Autodesk Fusion 360 part; units mm, degrees
(part 4 of 4)
  line L918 (235.694, -72.9326) -> (235.694, -74.9331)
  line L919 (235.694, -74.9331) -> (221.695, -74.9331)
  line L920 (221.695, -74.9331) -> (221.695, -72.9326)
  line L921 (221.695, -72.9326) -> (220.894, -72.9326)
  line L922 (220.894, -72.9326) -> (220.894, -69.8334)
  line L923 (220.894, -69.8334) -> (221.695, -69.8334)
  line L924 (221.695, -69.8334) -> (221.695, -64.0334)
  line L925 (221.695, -64.0334) -> (220.894, -64.0334)
  line L926 (220.894, -64.0334) -> (220.894, -60.9328)
  line L927 (220.894, -60.9328) -> (221.695, -60.9328)
  line L928 (135.97, -79.9828) -> (135.97, -77.9838)
  line L929 (135.97, -77.9838) -> (149.969, -77.9838)
  line L930 (149.969, -77.9838) -> (149.969, -79.9828)
  line L931 (149.969, -79.9828) -> (150.77, -79.9828)
  line L932 (150.77, -79.9828) -> (150.77, -83.0834)
  line L933 (150.77, -83.0834) -> (149.969, -83.0834)
  line L934 (149.969, -83.0834) -> (149.969, -88.8834)
  line L935 (149.969, -88.8834) -> (150.77, -88.8834)
  line L936 (150.77, -88.8834) -> (150.77, -91.9826)
  line L937 (150.77, -91.9826) -> (149.969, -91.9826)
  line L938 (149.969, -91.9826) -> (149.969, -93.9831)
  line L939 (149.969, -93.9831) -> (135.97, -93.9831)
  line L940 (135.97, -93.9831) -> (135.97, -91.9826)
  line L941 (135.97, -91.9826) -> (135.169, -91.9826)
  line L942 (135.169, -91.9826) -> (135.169, -88.8834)
  line L943 (135.169, -88.8834) -> (135.97, -88.8834)
  line L944 (135.97, -88.8834) -> (135.97, -83.0834)
  line L945 (135.97, -83.0834) -> (135.169, -83.0834)
  line L946 (135.169, -83.0834) -> (135.169, -79.9828)
  line L947 (135.169, -79.9828) -> (135.97, -79.9828)
  line L948 (69.2947, -60.9328) -> (69.2947, -58.9338)
  line L949 (69.2947, -58.9338) -> (83.294, -58.9338)
  line L950 (83.294, -58.9338) -> (83.294, -60.9328)
  line L951 (83.294, -60.9328) -> (84.0948, -60.9328)
  line L952 (84.0948, -60.9328) -> (84.0948, -64.0334)
  line L953 (84.0948, -64.0334) -> (83.294, -64.0334)
  line L954 (83.294, -64.0334) -> (83.294, -69.8334)
  line L955 (83.294, -69.8334) -> (84.0948, -69.8334)
  line L956 (84.0948, -69.8334) -> (84.0948, -72.9326)
  line L957 (84.0948, -72.9326) -> (83.294, -72.9326)
  line L958 (83.294, -72.9326) -> (83.294, -74.9331)
  line L959 (83.294, -74.9331) -> (69.2947, -74.9331)
  line L960 (69.2947, -74.9331) -> (69.2947, -72.9326)
  line L961 (69.2947, -72.9326) -> (68.4939, -72.9326)
  line L962 (68.4939, -72.9326) -> (68.4939, -69.8334)
  line L963 (68.4939, -69.8334) -> (69.2947, -69.8334)
  line L964 (69.2947, -69.8334) -> (69.2947, -64.0334)
  line L965 (69.2947, -64.0334) -> (68.4939, -64.0334)
  line L966 (68.4939, -64.0334) -> (68.4939, -60.9328)
  line L967 (68.4939, -60.9328) -> (69.2947, -60.9328)
  line L968 (169.307, -41.8828) -> (169.307, -39.8838)
  line L969 (169.307, -39.8838) -> (183.307, -39.8838)
  line L970 (183.307, -39.8838) -> (183.307, -41.8828)
  line L971 (183.307, -41.8828) -> (184.106, -41.8828)
  line L972 (184.106, -41.8828) -> (184.106, -44.9834)
  line L973 (184.106, -44.9834) -> (183.307, -44.9834)
  line L974 (183.307, -44.9834) -> (183.307, -50.7834)
  line L975 (183.307, -50.7834) -> (184.106, -50.7834)
  line L976 (184.106, -50.7834) -> (184.106, -53.8826)
  line L977 (184.106, -53.8826) -> (183.307, -53.8826)
  line L978 (183.307, -53.8826) -> (183.307, -55.8831)
  line L979 (183.307, -55.8831) -> (169.307, -55.8831)
  line L980 (169.307, -55.8831) -> (169.307, -53.8826)
  line L981 (169.307, -53.8826) -> (168.506, -53.8826)
  line L982 (168.506, -53.8826) -> (168.506, -50.7834)
  line L983 (168.506, -50.7834) -> (169.307, -50.7834)
  line L984 (169.307, -50.7834) -> (169.307, -44.9834)
  line L985 (169.307, -44.9834) -> (168.506, -44.9834)
  line L986 (168.506, -44.9834) -> (168.506, -41.8828)
  line L987 (168.506, -41.8828) -> (169.307, -41.8828)
  line L988 (150.257, -41.8828) -> (150.257, -39.8838)
  line L989 (150.257, -39.8838) -> (164.257, -39.8838)
  line L990 (164.257, -39.8838) -> (164.257, -41.8828)
  line L991 (164.257, -41.8828) -> (165.056, -41.8828)
  line L992 (165.056, -41.8828) -> (165.056, -44.9834)
  line L993 (165.056, -44.9834) -> (164.257, -44.9834)
  line L994 (164.257, -44.9834) -> (164.257, -50.7834)
  line L995 (164.257, -50.7834) -> (165.056, -50.7834)
  line L996 (165.056, -50.7834) -> (165.056, -53.8826)
  line L997 (165.056, -53.8826) -> (164.257, -53.8826)
  line L998 (164.257, -53.8826) -> (164.257, -55.8831)
  line L999 (164.257, -55.8831) -> (150.257, -55.8831)
  line L1000 (150.257, -55.8831) -> (150.257, -53.8826)
  line L1001 (150.257, -53.8826) -> (149.456, -53.8826)
  line L1002 (149.456, -53.8826) -> (149.456, -50.7834)
  line L1003 (149.456, -50.7834) -> (150.257, -50.7834)
  line L1004 (150.257, -50.7834) -> (150.257, -44.9834)
  line L1005 (150.257, -44.9834) -> (149.456, -44.9834)
  line L1006 (149.456, -44.9834) -> (149.456, -41.8828)
  line L1007 (149.456, -41.8828) -> (150.257, -41.8828)
  line L1008 (257.412, -41.8828) -> (257.412, -39.8838)
  line L1009 (257.412, -39.8838) -> (271.413, -39.8838)
  line L1010 (271.413, -39.8838) -> (271.413, -41.8828)
  line L1011 (271.413, -41.8828) -> (272.212, -41.8828)
  line L1012 (272.212, -41.8828) -> (272.212, -44.9834)
  line L1013 (272.212, -44.9834) -> (271.413, -44.9834)
  line L1014 (271.413, -44.9834) -> (271.413, -45.5828)
  line L1015 (271.413, -45.5828) -> (272.937, -45.5828)
  line L1016 (272.937, -45.5828) -> (272.937, -41.1138)
  line L1017 (272.937, -41.1138) -> (274.662, -41.1138)
  line L1018 (274.662, -41.1138) -> (274.662, -39.9136)
  line L1019 (274.662, -39.9136) -> (277.963, -39.9136)
  line L1020 (277.963, -39.9136) -> (277.963, -41.1138)
  line L1021 (277.963, -41.1138) -> (279.688, -41.1138)
  line L1022 (279.688, -41.1138) -> (279.688, -47.3837)
  line L1023 (279.688, -47.3837) -> (280.512, -47.3837)
  line L1024 (280.512, -47.3837) -> (280.512, -50.1826)
  line L1025 (280.512, -50.1826) -> (279.688, -50.1826)
  line L1026 (279.688, -50.1826) -> (279.688, -53.4127)
  line L1027 (279.688, -53.4127) -> (272.937, -53.4127)
  line L1028 (272.937, -53.4127) -> (272.937, -50.1826)
  line L1029 (272.937, -50.1826) -> (271.413, -50.1826)
  line L1030 (271.413, -50.1826) -> (271.413, -50.7834)
  line L1031 (271.413, -50.7834) -> (272.212, -50.7834)
  line L1032 (272.212, -50.7834) -> (272.212, -53.8826)
  line L1033 (272.212, -53.8826) -> (271.413, -53.8826)
  line L1034 (271.413, -53.8826) -> (271.413, -55.8831)
  line L1035 (271.413, -55.8831) -> (257.412, -55.8831)
  line L1036 (257.412, -55.8831) -> (257.412, -53.8826)
  line L1037 (257.412, -53.8826) -> (256.611, -53.8826)
  line L1038 (256.611, -53.8826) -> (256.611, -50.7834)
  line L1039 (256.611, -50.7834) -> (257.412, -50.7834)
  line L1040 (257.412, -50.7834) -> (257.412, -50.1826)
  line L1041 (257.412, -50.1826) -> (255.888, -50.1826)
  line L1042 (255.888, -50.1826) -> (255.888, -53.4127)
  line L1043 (255.888, -53.4127) -> (249.137, -53.4127)
  line L1044 (249.137, -53.4127) -> (249.137, -50.1826)
  line L1045 (249.137, -50.1826) -> (248.313, -50.1826)
  line L1046 (248.313, -50.1826) -> (248.313, -47.3837)
  line L1047 (248.313, -47.3837) -> (249.137, -47.3837)
  line L1048 (249.137, -47.3837) -> (249.137, -41.1138)
  line L1049 (249.137, -41.1138) -> (250.862, -41.1138)
  line L1050 (250.862, -41.1138) -> (250.862, -39.9136)
  line L1051 (250.862, -39.9136) -> (254.161, -39.9136)
  line L1052 (254.161, -39.9136) -> (254.161, -41.1138)
  line L1053 (254.161, -41.1138) -> (255.888, -41.1138)
  line L1054 (255.888, -41.1138) -> (255.888, -45.5828)
  line L1055 (255.888, -45.5828) -> (257.412, -45.5828)
  line L1056 (257.412, -45.5828) -> (257.412, -44.9834)
  line L1057 (257.412, -44.9834) -> (256.611, -44.9834)
  line L1058 (256.611, -44.9834) -> (256.611, -41.8828)
  line L1059 (256.611, -41.8828) -> (257.412, -41.8828)
  line L1060 (83.5822, -22.8327) -> (83.5822, -20.8336)
  line L1061 (83.5822, -20.8336) -> (97.5815, -20.8336)
  line L1062 (97.5815, -20.8336) -> (97.5815, -22.8327)
  line L1063 (97.5815, -22.8327) -> (98.3809, -22.8327)
  line L1064 (98.3809, -22.8327) -> (98.3809, -25.9333)
  line L1065 (98.3809, -25.9333) -> (97.5815, -25.9333)
  line L1066 (97.5815, -25.9333) -> (97.5815, -31.7348)
  line L1067 (97.5815, -31.7348) -> (98.3809, -31.7348)
  line L1068 (98.3809, -31.7348) -> (98.3809, -34.8327)
  line L1069 (98.3809, -34.8327) -> (97.5815, -34.8327)
  line L1070 (97.5815, -34.8327) -> (97.5815, -36.833)
  line L1071 (97.5815, -36.833) -> (83.5822, -36.833)
  line L1072 (83.5822, -36.833) -> (83.5822, -34.8327)
  line L1073 (83.5822, -34.8327) -> (82.7814, -34.8327)
  line L1074 (82.7814, -34.8327) -> (82.7814, -31.7348)
  line L1075 (82.7814, -31.7348) -> (83.5822, -31.7348)
  line L1076 (83.5822, -31.7348) -> (83.5822, -25.9333)
  line L1077 (83.5822, -25.9333) -> (82.7814, -25.9333)
  line L1078 (82.7814, -25.9333) -> (82.7814, -22.8327)
  line L1079 (82.7814, -22.8327) -> (83.5822, -22.8327)
  line L1080 (288.37, -22.8327) -> (288.37, -20.8336)
  line L1081 (288.37, -20.8336) -> (302.369, -20.8336)
  line L1082 (302.369, -20.8336) -> (302.369, -22.8327)
  line L1083 (302.369, -22.8327) -> (303.17, -22.8327)
  line L1084 (303.17, -22.8327) -> (303.17, -25.9333)
  line L1085 (303.17, -25.9333) -> (302.369, -25.9333)
  line L1086 (302.369, -25.9333) -> (302.369, -31.7348)
  line L1087 (302.369, -31.7348) -> (303.17, -31.7348)
  line L1088 (303.17, -31.7348) -> (303.17, -34.8327)
  line L1089 (303.17, -34.8327) -> (302.369, -34.8327)
  line L1090 (302.369, -34.8327) -> (302.369, -36.833)
  line L1091 (302.369, -36.833) -> (288.37, -36.833)
  line L1092 (288.37, -36.833) -> (288.37, -34.8327)
  line L1093 (288.37, -34.8327) -> (287.569, -34.8327)
  line L1094 (287.569, -34.8327) -> (287.569, -31.7348)
  line L1095 (287.569, -31.7348) -> (288.37, -31.7348)
  line L1096 (288.37, -31.7348) -> (288.37, -25.9333)
  line L1097 (288.37, -25.9333) -> (287.569, -25.9333)
  line L1098 (287.569, -25.9333) -> (287.569, -22.8327)
  line L1099 (287.569, -22.8327) -> (288.37, -22.8327)
  line L1100 (269.32, -22.8327) -> (269.32, -20.8336)
  line L1101 (269.32, -20.8336) -> (283.319, -20.8336)
  line L1102 (283.319, -20.8336) -> (283.319, -22.8327)
  line L1103 (283.319, -22.8327) -> (284.12, -22.8327)
  line L1104 (284.12, -22.8327) -> (284.12, -25.9333)
  line L1105 (284.12, -25.9333) -> (283.319, -25.9333)
  line L1106 (283.319, -25.9333) -> (283.319, -31.7348)
  line L1107 (283.319, -31.7348) -> (284.12, -31.7348)
  line L1108 (284.12, -31.7348) -> (284.12, -34.8327)
  line L1109 (284.12, -34.8327) -> (283.319, -34.8327)
  line L1110 (283.319, -34.8327) -> (283.319, -36.833)
  line L1111 (283.319, -36.833) -> (269.32, -36.833)
  line L1112 (269.32, -36.833) -> (269.32, -34.8327)
  line L1113 (269.32, -34.8327) -> (268.519, -34.8327)
  line L1114 (268.519, -34.8327) -> (268.519, -31.7348)
  line L1115 (268.519, -31.7348) -> (269.32, -31.7348)
  line L1116 (269.32, -31.7348) -> (269.32, -25.9333)
  line L1117 (269.32, -25.9333) -> (268.519, -25.9333)
  line L1118 (268.519, -25.9333) -> (268.519, -22.8327)
  line L1119 (268.519, -22.8327) -> (269.32, -22.8327)
  line L1120 (250.27, -3.7827) -> (250.27, -1.7836)
  line L1121 (250.27, -1.7836) -> (264.269, -1.7836)
  line L1122 (264.269, -1.7836) -> (264.269, -3.7827)
  line L1123 (264.269, -3.7827) -> (265.07, -3.7827)
  line L1124 (265.07, -3.7827) -> (265.07, -6.8833)
  line L1125 (265.07, -6.8833) -> (264.269, -6.8833)
  line L1126 (264.269, -6.8833) -> (264.269, -12.6848)
  line L1127 (264.269, -12.6848) -> (265.07, -12.6848)
  line L1128 (265.07, -12.6848) -> (265.07, -15.7827)
  line L1129 (265.07, -15.7827) -> (264.269, -15.7827)
  line L1130 (264.269, -15.7827) -> (264.269, -17.7831)
  line L1131 (264.269, -17.7831) -> (250.27, -17.7831)
  line L1132 (250.27, -17.7831) -> (250.27, -15.7827)
  line L1133 (250.27, -15.7827) -> (249.469, -15.7827)
  line L1134 (249.469, -15.7827) -> (249.469, -12.6848)
  line L1135 (249.469, -12.6848) -> (250.27, -12.6848)
  line L1136 (250.27, -12.6848) -> (250.27, -6.8833)
  line L1137 (250.27, -6.8833) -> (249.469, -6.8833)
  line L1138 (249.469, -6.8833) -> (249.469, -3.7827)
  line L1139 (249.469, -3.7827) -> (250.27, -3.7827)
  line L1140 (14.5259, -22.8327) -> (14.5259, -20.8336)
  line L1141 (14.5259, -20.8336) -> (28.5254, -20.8336)
  line L1142 (28.5254, -20.8336) -> (28.5254, -22.8327)
  line L1143 (28.5254, -22.8327) -> (29.326, -22.8327)
  line L1144 (29.326, -22.8327) -> (29.326, -25.9333)
  line L1145 (29.326, -25.9333) -> (28.5254, -25.9333)
  line L1146 (28.5254, -25.9333) -> (28.5254, -26.5327)
  line L1147 (28.5254, -26.5327) -> (30.0509, -26.5327)
  line L1148 (30.0509, -26.5327) -> (30.0509, -22.0638)
  line L1149 (30.0509, -22.0638) -> (31.7748, -22.0638)
  line L1150 (31.7748, -22.0638) -> (31.7748, -20.8635)
  line L1151 (31.7748, -20.8635) -> (35.0752, -20.8635)
  line L1152 (35.0752, -20.8635) -> (35.0752, -22.0638)
  line L1153 (35.0752, -22.0638) -> (36.8004, -22.0638)
  line L1154 (36.8004, -22.0638) -> (36.8004, -28.3338)
  line L1155 (36.8004, -28.3338) -> (37.6259, -28.3338)
  line L1156 (37.6259, -28.3338) -> (37.6259, -31.1326)
  line L1157 (37.6259, -31.1326) -> (36.8004, -31.1326)
  line L1158 (36.8004, -31.1326) -> (36.8004, -34.3628)
  line L1159 (36.8004, -34.3628) -> (30.0509, -34.3628)
  line L1160 (30.0509, -34.3628) -> (30.0509, -31.1326)
  line L1161 (30.0509, -31.1326) -> (28.5254, -31.1326)
  line L1162 (28.5254, -31.1326) -> (28.5254, -31.7348)
  line L1163 (28.5254, -31.7348) -> (29.326, -31.7348)
  line L1164 (29.326, -31.7348) -> (29.326, -34.8327)
  line L1165 (29.326, -34.8327) -> (28.5254, -34.8327)
  line L1166 (28.5254, -34.8327) -> (28.5254, -36.833)
  line L1167 (28.5254, -36.833) -> (14.5259, -36.833)
  line L1168 (14.5259, -36.833) -> (14.5259, -34.8327)
  line L1169 (14.5259, -34.8327) -> (13.7253, -34.8327)
  line L1170 (13.7253, -34.8327) -> (13.7253, -31.7348)
  line L1171 (13.7253, -31.7348) -> (14.5259, -31.7348)
  line L1172 (14.5259, -31.7348) -> (14.5259, -31.1326)
  line L1173 (14.5259, -31.1326) -> (13.0004, -31.1326)
  line L1174 (13.0004, -31.1326) -> (13.0004, -34.3628)
  line L1175 (13.0004, -34.3628) -> (6.2508, -34.3628)
  line L1176 (6.2508, -34.3628) -> (6.2508, -31.1326)
  line L1177 (6.2508, -31.1326) -> (5.4253, -31.1326)
  line L1178 (5.4253, -31.1326) -> (5.4253, -28.3338)
  line L1179 (5.4253, -28.3338) -> (6.2508, -28.3338)
  line L1180 (6.2508, -28.3338) -> (6.2508, -22.0638)
  line L1181 (6.2508, -22.0638) -> (7.9761, -22.0638)
  line L1182 (7.9761, -22.0638) -> (7.9761, -20.8635)
  line L1183 (7.9761, -20.8635) -> (11.2751, -20.8635)
  line L1184 (11.2751, -20.8635) -> (11.2751, -22.0638)
  line L1185 (11.2751, -22.0638) -> (13.0004, -22.0638)
  line L1186 (13.0004, -22.0638) -> (13.0004, -26.5327)
  line L1187 (13.0004, -26.5327) -> (14.5259, -26.5327)
  line L1188 (14.5259, -26.5327) -> (14.5259, -25.9333)
  line L1189 (14.5259, -25.9333) -> (13.7253, -25.9333)
  line L1190 (13.7253, -25.9333) -> (13.7253, -22.8327)
  line L1191 (13.7253, -22.8327) -> (14.5259, -22.8327)
  line L1192 (193.12, -3.7827) -> (193.12, -1.7836)
  line L1193 (193.12, -1.7836) -> (207.119, -1.7836)
  line L1194 (207.119, -1.7836) -> (207.119, -3.7827)
  line L1195 (207.119, -3.7827) -> (207.92, -3.7827)
  line L1196 (207.92, -3.7827) -> (207.92, -6.8833)
  line L1197 (207.92, -6.8833) -> (207.119, -6.8833)
  line L1198 (207.119, -6.8833) -> (207.119, -12.6848)
  line L1199 (207.119, -12.6848) -> (207.92, -12.6848)
  line L1200 (207.92, -12.6848) -> (207.92, -15.7827)
  line L1201 (207.92, -15.7827) -> (207.119, -15.7827)
  line L1202 (207.119, -15.7827) -> (207.119, -17.7831)
  line L1203 (207.119, -17.7831) -> (193.12, -17.7831)
  line L1204 (193.12, -17.7831) -> (193.12, -15.7827)
  line L1205 (193.12, -15.7827) -> (192.319, -15.7827)
  line L1206 (192.319, -15.7827) -> (192.319, -12.6848)
  line L1207 (192.319, -12.6848) -> (193.12, -12.6848)
  line L1208 (193.12, -12.6848) -> (193.12, -6.8833)
  line L1209 (193.12, -6.8833) -> (192.319, -6.8833)
  line L1210 (192.319, -6.8833) -> (192.319, -3.7827)
  line L1211 (192.319, -3.7827) -> (193.12, -3.7827)
  line L1212 (231.22, -3.7827) -> (231.22, -1.7836)
  line L1213 (231.22, -1.7836) -> (245.219, -1.7836)
  line L1214 (245.219, -1.7836) -> (245.219, -3.7827)
  line L1215 (245.219, -3.7827) -> (246.02, -3.7827)
  line L1216 (246.02, -3.7827) -> (246.02, -6.8833)
  line L1217 (246.02, -6.8833) -> (245.219, -6.8833)
  line L1218 (245.219, -6.8833) -> (245.219, -12.6848)
  line L1219 (245.219, -12.6848) -> (246.02, -12.6848)
  line L1220 (246.02, -12.6848) -> (246.02, -15.7827)
  line L1221 (246.02, -15.7827) -> (245.219, -15.7827)
  line L1222 (245.219, -15.7827) -> (245.219, -17.7831)
  line L1223 (245.219, -17.7831) -> (231.22, -17.7831)
  line L1224 (231.22, -17.7831) -> (231.22, -15.7827)
  line L1225 (231.22, -15.7827) -> (230.419, -15.7827)
  line L1226 (230.419, -15.7827) -> (230.419, -12.6848)
  line L1227 (230.419, -12.6848) -> (231.22, -12.6848)
  line L1228 (231.22, -12.6848) -> (231.22, -6.8833)
  line L1229 (231.22, -6.8833) -> (230.419, -6.8833)
  line L1230 (230.419, -6.8833) -> (230.419, -3.7827)
  line L1231 (230.419, -3.7827) -> (231.22, -3.7827)
  line L1232 (193.12, -79.9828) -> (193.12, -77.9838)
  line L1233 (193.12, -77.9838) -> (207.119, -77.9838)
  line L1234 (207.119, -77.9838) -> (207.119, -79.9828)
  line L1235 (207.119, -79.9828) -> (207.92, -79.9828)
  line L1236 (207.92, -79.9828) -> (207.92, -83.0834)
  line L1237 (207.92, -83.0834) -> (207.119, -83.0834)
  line L1238 (207.119, -83.0834) -> (207.119, -88.8834)
  line L1239 (207.119, -88.8834) -> (207.92, -88.8834)
  line L1240 (207.92, -88.8834) -> (207.92, -91.9826)
  line L1241 (207.92, -91.9826) -> (207.119, -91.9826)
  line L1242 (207.119, -91.9826) -> (207.119, -93.9831)
  line L1243 (207.119, -93.9831) -> (193.12, -93.9831)
  line L1244 (193.12, -93.9831) -> (193.12, -91.9826)
  line L1245 (193.12, -91.9826) -> (192.319, -91.9826)
  line L1246 (192.319, -91.9826) -> (192.319, -88.8834)
  line L1247 (192.319, -88.8834) -> (193.12, -88.8834)
  line L1248 (193.12, -88.8834) -> (193.12, -83.0834)
  line L1249 (193.12, -83.0834) -> (192.319, -83.0834)
  line L1250 (192.319, -83.0834) -> (192.319, -79.9828)
  line L1251 (192.319, -79.9828) -> (193.12, -79.9828)
  line L1252 (231.22, -79.9828) -> (231.22, -77.9838)
  line L1253 (231.22, -77.9838) -> (245.219, -77.9838)
  line L1254 (245.219, -77.9838) -> (245.219, -79.9828)
  line L1255 (245.219, -79.9828) -> (246.02, -79.9828)
  line L1256 (246.02, -79.9828) -> (246.02, -83.0834)
  line L1257 (246.02, -83.0834) -> (245.219, -83.0834)
  line L1258 (245.219, -83.0834) -> (245.219, -88.8834)
  line L1259 (245.219, -88.8834) -> (246.02, -88.8834)
  line L1260 (246.02, -88.8834) -> (246.02, -91.9826)
  line L1261 (246.02, -91.9826) -> (245.219, -91.9826)
  line L1262 (245.219, -91.9826) -> (245.219, -93.9831)
  line L1263 (245.219, -93.9831) -> (231.22, -93.9831)
  line L1264 (231.22, -93.9831) -> (231.22, -91.9826)
  line L1265 (231.22, -91.9826) -> (230.419, -91.9826)
  line L1266 (230.419, -91.9826) -> (230.419, -88.8834)
  line L1267 (230.419, -88.8834) -> (231.22, -88.8834)
  line L1268 (231.22, -88.8834) -> (231.22, -83.0834)
  line L1269 (231.22, -83.0834) -> (230.419, -83.0834)
  line L1270 (230.419, -83.0834) -> (230.419, -79.9828)
  line L1271 (230.419, -79.9828) -> (231.22, -79.9828)
  line L1272 (59.7697, -79.9828) -> (59.7697, -77.9838)
  line L1273 (59.7697, -77.9838) -> (73.769, -77.9838)
  line L1274 (73.769, -77.9838) -> (73.769, -79.9828)
  line L1275 (73.769, -79.9828) -> (74.5698, -79.9828)
  line L1276 (74.5698, -79.9828) -> (74.5698, -83.0834)
  line L1277 (74.5698, -83.0834) -> (73.769, -83.0834)
  line L1278 (73.769, -83.0834) -> (73.769, -88.8834)
  line L1279 (73.769, -88.8834) -> (74.5698, -88.8834)
  line L1280 (74.5698, -88.8834) -> (74.5698, -91.9826)
  line L1281 (74.5698, -91.9826) -> (73.769, -91.9826)
  line L1282 (73.769, -91.9826) -> (73.769, -93.9831)
  line L1283 (73.769, -93.9831) -> (59.7697, -93.9831)
  line L1284 (59.7697, -93.9831) -> (59.7697, -91.9826)
  line L1285 (59.7697, -91.9826) -> (58.9689, -91.9826)
  line L1286 (58.9689, -91.9826) -> (58.9689, -88.8834)
  line L1287 (58.9689, -88.8834) -> (59.7697, -88.8834)
  line L1288 (59.7697, -88.8834) -> (59.7697, -83.0834)
  line L1289 (59.7697, -83.0834) -> (58.9689, -83.0834)
  line L1290 (58.9689, -83.0834) -> (58.9689, -79.9828)
  line L1291 (58.9689, -79.9828) -> (59.7697, -79.9828)
  line L1292 (183.595, -60.9328) -> (183.595, -58.9338)
  line L1293 (183.595, -58.9338) -> (197.594, -58.9338)
  line L1294 (197.594, -58.9338) -> (197.594, -60.9328)
  line L1295 (197.594, -60.9328) -> (198.395, -60.9328)
  line L1296 (198.395, -60.9328) -> (198.395, -64.0334)
  line L1297 (198.395, -64.0334) -> (197.594, -64.0334)
  line L1298 (197.594, -64.0334) -> (197.594, -69.8334)
  line L1299 (197.594, -69.8334) -> (198.395, -69.8334)
  line L1300 (198.395, -69.8334) -> (198.395, -72.9326)
  line L1301 (198.395, -72.9326) -> (197.594, -72.9326)
  line L1302 (197.594, -72.9326) -> (197.594, -74.9331)
  line L1303 (197.594, -74.9331) -> (183.595, -74.9331)
  line L1304 (183.595, -74.9331) -> (183.595, -72.9326)
  line L1305 (183.595, -72.9326) -> (182.794, -72.9326)
  line L1306 (182.794, -72.9326) -> (182.794, -69.8334)
  line L1307 (182.794, -69.8334) -> (183.595, -69.8334)
  line L1308 (183.595, -69.8334) -> (183.595, -64.0334)
  line L1309 (183.595, -64.0334) -> (182.794, -64.0334)
  line L1310 (182.794, -64.0334) -> (182.794, -60.9328)
  line L1311 (182.794, -60.9328) -> (183.595, -60.9328)
  line L1312 (164.545, -60.9328) -> (164.545, -58.9338)
  line L1313 (164.545, -58.9338) -> (178.544, -58.9338)
  line L1314 (178.544, -58.9338) -> (178.544, -60.9328)
  line L1315 (178.544, -60.9328) -> (179.345, -60.9328)
  line L1316 (179.345, -60.9328) -> (179.345, -64.0334)
  line L1317 (179.345, -64.0334) -> (178.544, -64.0334)
  line L1318 (178.544, -64.0334) -> (178.544, -69.8334)
  line L1319 (178.544, -69.8334) -> (179.345, -69.8334)
  line L1320 (179.345, -69.8334) -> (179.345, -72.9326)
  line L1321 (179.345, -72.9326) -> (178.544, -72.9326)
  line L1322 (178.544, -72.9326) -> (178.544, -74.9331)
  line L1323 (178.544, -74.9331) -> (164.545, -74.9331)
  line L1324 (164.545, -74.9331) -> (164.545, -72.9326)
  line L1325 (164.545, -72.9326) -> (163.744, -72.9326)
  line L1326 (163.744, -72.9326) -> (163.744, -69.8334)
  line L1327 (163.744, -69.8334) -> (164.545, -69.8334)
  line L1328 (164.545, -69.8334) -> (164.545, -64.0334)
  line L1329 (164.545, -64.0334) -> (163.744, -64.0334)
  line L1330 (163.744, -64.0334) -> (163.744, -60.9328)
  line L1331 (163.744, -60.9328) -> (164.545, -60.9328)
  line L1332 (145.495, -60.9328) -> (145.495, -58.9338)
  line L1333 (145.495, -58.9338) -> (159.494, -58.9338)
  line L1334 (159.494, -58.9338) -> (159.494, -60.9328)
  line L1335 (159.494, -60.9328) -> (160.295, -60.9328)
  line L1336 (160.295, -60.9328) -> (160.295, -64.0334)
  line L1337 (160.295, -64.0334) -> (159.494, -64.0334)
  line L1338 (159.494, -64.0334) -> (159.494, -69.8334)
  line L1339 (159.494, -69.8334) -> (160.295, -69.8334)
  line L1340 (160.295, -69.8334) -> (160.295, -72.9326)
  line L1341 (160.295, -72.9326) -> (159.494, -72.9326)
  line L1342 (159.494, -72.9326) -> (159.494, -74.9331)
  line L1343 (159.494, -74.9331) -> (145.495, -74.9331)
  line L1344 (145.495, -74.9331) -> (145.495, -72.9326)
  line L1345 (145.495, -72.9326) -> (144.694, -72.9326)
  line L1346 (144.694, -72.9326) -> (144.694, -69.8334)
  line L1347 (144.694, -69.8334) -> (145.495, -69.8334)
  line L1348 (145.495, -69.8334) -> (145.495, -64.0334)
  line L1349 (145.495, -64.0334) -> (144.694, -64.0334)
  line L1350 (144.694, -64.0334) -> (144.694, -60.9328)
  line L1351 (144.694, -60.9328) -> (145.495, -60.9328)
  line L1352 (2.6197, -79.9828) -> (2.6197, -77.9838)
  line L1353 (2.6197, -77.9838) -> (16.6192, -77.9838)
  line L1354 (16.6192, -77.9838) -> (16.6192, -79.9828)
  line L1355 (16.6192, -79.9828) -> (17.4198, -79.9828)
  line L1356 (17.4198, -79.9828) -> (17.4198, -83.0834)
  line L1357 (17.4198, -83.0834) -> (16.6192, -83.0834)
  line L1358 (16.6192, -83.0834) -> (16.6192, -88.8834)
  line L1359 (16.6192, -88.8834) -> (17.4198, -88.8834)
  line L1360 (17.4198, -88.8834) -> (17.4198, -91.9826)
  line L1361 (17.4198, -91.9826) -> (16.6192, -91.9826)
  line L1362 (16.6192, -91.9826) -> (16.6192, -93.9831)
  line L1363 (16.6192, -93.9831) -> (2.6196, -93.9831)
  line L1364 (2.6197, -93.9831) -> (2.6197, -91.9826)
  line L1365 (2.6197, -91.9826) -> (1.819, -91.9826)
  line L1366 (1.819, -91.9826) -> (1.819, -88.8834)
  line L1367 (1.819, -88.8834) -> (2.6197, -88.8834)
  line L1368 (2.6197, -88.8834) -> (2.6197, -83.0834)
  line L1369 (2.6197, -83.0834) -> (1.819, -83.0834)
  line L1370 (1.819, -83.0834) -> (1.819, -79.9828)
  line L1371 (1.819, -79.9828) -> (2.6197, -79.9828)
  line L1372 (97.8683, -79.9828) -> (97.8683, -77.9838)
  line L1373 (97.8683, -77.9838) -> (111.869, -77.9838)
  line L1374 (111.869, -77.9838) -> (111.869, -79.9828)
  line L1375 (111.869, -79.9828) -> (112.668, -79.9828)
  line L1376 (112.668, -79.9828) -> (112.668, -83.0834)
  line L1377 (112.668, -83.0834) -> (111.869, -83.0834)
  line L1378 (111.869, -83.0834) -> (111.869, -88.8834)
  line L1379 (111.869, -88.8834) -> (112.668, -88.8834)
  line L1380 (112.668, -88.8834) -> (112.668, -91.9826)
  line L1381 (112.668, -91.9826) -> (111.869, -91.9826)
  line L1382 (111.869, -91.9826) -> (111.869, -93.9831)
  line L1383 (111.869, -93.9831) -> (97.8683, -93.9831)
  line L1384 (97.8683, -93.9831) -> (97.8683, -91.9826)
  line L1385 (97.8683, -91.9826) -> (97.0689, -91.9826)
  line L1386 (97.0689, -91.9826) -> (97.0689, -88.8834)
  line L1387 (97.0689, -88.8834) -> (97.8683, -88.8834)
  line L1388 (97.8683, -88.8834) -> (97.8683, -83.0834)
  line L1389 (97.8683, -83.0834) -> (97.0689, -83.0834)
  line L1390 (97.0689, -83.0834) -> (97.0689, -79.9828)
  line L1391 (97.0689, -79.9828) -> (97.8683, -79.9828)
  line L1392 (78.8197, -79.9828) -> (78.8197, -77.9838)
  line L1393 (78.8197, -77.9838) -> (92.819, -77.9838)
  line L1394 (92.819, -77.9838) -> (92.819, -79.9828)
  line L1395 (92.819, -79.9828) -> (93.6184, -79.9828)
  line L1396 (93.6184, -79.9828) -> (93.6184, -83.0834)
  line L1397 (93.6184, -83.0834) -> (92.819, -83.0834)
  line L1398 (92.819, -83.0834) -> (92.819, -88.8834)
  line L1399 (92.819, -88.8834) -> (93.6184, -88.8834)
  line L1400 (93.6184, -88.8834) -> (93.6184, -91.9826)
  line L1401 (93.6184, -91.9826) -> (92.819, -91.9826)
  line L1402 (92.819, -91.9826) -> (92.819, -93.9831)
  line L1403 (92.819, -93.9831) -> (78.8197, -93.9831)
  line L1404 (78.8197, -93.9831) -> (78.8197, -91.9826)
  line L1405 (78.8197, -91.9826) -> (78.0189, -91.9826)
  line L1406 (78.0189, -91.9826) -> (78.0189, -88.8834)
  line L1407 (78.0189, -88.8834) -> (78.8197, -88.8834)
  line L1408 (78.8197, -88.8834) -> (78.8197, -83.0834)
  line L1409 (78.8197, -83.0834) -> (78.0189, -83.0834)
  line L1410 (78.0189, -83.0834) -> (78.0189, -79.9828)
  line L1411 (78.0189, -79.9828) -> (78.8197, -79.9828)
  line L1412 (50.2447, -60.9328) -> (50.2447, -58.9338)
  line L1413 (50.2447, -58.9338) -> (64.244, -58.9338)
  line L1414 (64.244, -58.9338) -> (64.244, -60.9328)
  line L1415 (64.244, -60.9328) -> (65.0448, -60.9328)
  line L1416 (65.0448, -60.9328) -> (65.0448, -64.0334)
  line L1417 (65.0448, -64.0334) -> (64.244, -64.0334)
  line L1418 (64.244, -64.0334) -> (64.244, -69.8334)
  line L1419 (64.244, -69.8334) -> (65.0448, -69.8334)
  line L1420 (65.0448, -69.8334) -> (65.0448, -72.9326)
  line L1421 (65.0448, -72.9326) -> (64.244, -72.9326)
  line L1422 (64.244, -72.9326) -> (64.244, -74.9331)
  line L1423 (64.244, -74.9331) -> (50.2447, -74.9331)
  line L1424 (50.2447, -74.9331) -> (50.2447, -72.9326)
  line L1425 (50.2447, -72.9326) -> (49.4439, -72.9326)
  line L1426 (49.4439, -72.9326) -> (49.4439, -69.8334)
  line L1427 (49.4439, -69.8334) -> (50.2447, -69.8334)
  line L1428 (50.2447, -69.8334) -> (50.2447, -64.0334)
  line L1429 (50.2447, -64.0334) -> (49.4439, -64.0334)
  line L1430 (49.4439, -64.0334) -> (49.4439, -60.9328)
  line L1431 (49.4439, -60.9328) -> (50.2447, -60.9328)
  line L1432 (31.1947, -60.9328) -> (31.1947, -58.9338)
  line L1433 (31.1947, -58.9338) -> (45.194, -58.9338)
  line L1434 (45.194, -58.9338) -> (45.194, -60.9328)
  line L1435 (45.194, -60.9328) -> (45.9948, -60.9328)
  line L1436 (45.9948, -60.9328) -> (45.9948, -64.0334)
  line L1437 (45.9948, -64.0334) -> (45.194, -64.0334)
  line L1438 (45.194, -64.0334) -> (45.194, -69.8334)
  line L1439 (45.194, -69.8334) -> (45.9948, -69.8334)
  line L1440 (45.9948, -69.8334) -> (45.9948, -72.9326)
  line L1441 (45.9948, -72.9326) -> (45.194, -72.9326)
  line L1442 (45.194, -72.9326) -> (45.194, -74.9331)
  line L1443 (45.194, -74.9331) -> (31.1947, -74.9331)
  line L1444 (31.1947, -74.9331) -> (31.1947, -72.9326)
  line L1445 (31.1947, -72.9326) -> (30.394, -72.9326)
  line L1446 (30.394, -72.9326) -> (30.394, -69.8334)
  line L1447 (30.394, -69.8334) -> (31.1947, -69.8334)
  line L1448 (31.1947, -69.8334) -> (31.1947, -64.0334)
  line L1449 (31.1947, -64.0334) -> (30.394, -64.0334)
  line L1450 (30.394, -64.0334) -> (30.394, -60.9328)
  line L1451 (30.394, -60.9328) -> (31.1947, -60.9328)
  line L1452 (155.02, -79.9828) -> (155.02, -77.9838)
  line L1453 (155.02, -77.9838) -> (169.019, -77.9838)
  line L1454 (169.019, -77.9838) -> (169.019, -79.9828)
  line L1455 (169.019, -79.9828) -> (169.82, -79.9828)
  line L1456 (169.82, -79.9828) -> (169.82, -83.0834)
  line L1457 (169.82, -83.0834) -> (169.019, -83.0834)
  line L1458 (169.019, -83.0834) -> (169.019, -88.8834)
  line L1459 (169.019, -88.8834) -> (169.82, -88.8834)
  line L1460 (169.82, -88.8834) -> (169.82, -91.9826)
  line L1461 (169.82, -91.9826) -> (169.019, -91.9826)
  line L1462 (169.019, -91.9826) -> (169.019, -93.9831)
  line L1463 (169.019, -93.9831) -> (155.02, -93.9831)
  line L1464 (155.02, -93.9831) -> (155.02, -91.9826)
  line L1465 (155.02, -91.9826) -> (154.219, -91.9826)
  line L1466 (154.219, -91.9826) -> (154.219, -88.8834)
  line L1467 (154.219, -88.8834) -> (155.02, -88.8834)
  line L1468 (155.02, -88.8834) -> (155.02, -83.0834)
  line L1469 (155.02, -83.0834) -> (154.219, -83.0834)
  line L1470 (154.219, -83.0834) -> (154.219, -79.9828)
  line L1471 (154.219, -79.9828) -> (155.02, -79.9828)
  line L1472 (264.557, -60.9328) -> (264.557, -58.9338)
  line L1473 (264.557, -58.9338) -> (278.557, -58.9338)
  line L1474 (278.557, -58.9338) -> (278.557, -60.9328)
  line L1475 (278.557, -60.9328) -> (279.356, -60.9328)
  line L1476 (279.356, -60.9328) -> (279.356, -64.0334)
  line L1477 (279.356, -64.0334) -> (278.557, -64.0334)
  line L1478 (278.557, -64.0334) -> (278.557, -69.8334)
  line L1479 (278.557, -69.8334) -> (279.356, -69.8334)
  line L1480 (279.356, -69.8334) -> (279.356, -72.9326)
  line L1481 (279.356, -72.9326) -> (278.557, -72.9326)
  line L1482 (278.557, -72.9326) -> (278.557, -74.9331)
  line L1483 (278.557, -74.9331) -> (264.557, -74.9331)
  line L1484 (264.557, -74.9331) -> (264.557, -72.9326)
  line L1485 (264.557, -72.9326) -> (263.756, -72.9326)
  line L1486 (263.756, -72.9326) -> (263.756, -69.8334)
  line L1487 (263.756, -69.8334) -> (264.557, -69.8334)
  line L1488 (264.557, -69.8334) -> (264.557, -64.0334)
  line L1489 (264.557, -64.0334) -> (263.756, -64.0334)
  line L1490 (263.756, -64.0334) -> (263.756, -60.9328)
  line L1491 (263.756, -60.9328) -> (264.557, -60.9328)
  line L1492 (284, -77) -> (250, -77)
  line L1493 (250, -77) -> (250, -95)
  line L1494 (250, -95) -> (284, -95)
  line L1495 (284, -95) -> (284, -77)
  line L1496 (284, -77) -> (250, -77)
  line L1497 (250, -77) -> (250, -95)
  line L1498 (250, -95) -> (284, -95)
  line L1499 (284, -95) -> (284, -77)
  line L1500 (284, -77) -> (250, -77)
  line L1501 (250, -77) -> (250, -95)
  line L1502 (250, -95) -> (284, -95)
  line L1503 (284, -95) -> (284, -77)
  line L1504 (284, -77) -> (250, -77)
  line L1505 (250, -77) -> (250, -95)
  line L1506 (250, -95) -> (284, -95)
  line L1507 (284, -95) -> (284, -77)
  line L1508 (284, -95) -> (250, -95)
  line L1509 (250, -95) -> (250, -77)
  line L1510 (250, -77) -> (284, -77)
  line L1511 (284, -77) -> (284, -95)
  line L1512 (281, -57) -> (248, -57)
  line L1513 (248, -57) -> (248, -39)
  line L1514 (248, -39) -> (281, -39)
  line L1515 (281, -39) -> (281, -57)
  line L1516 (248, -57) -> (281, -57)
  line L1517 (281, -57) -> (281, -39)
  line L1518 (281, -39) -> (248, -39)
  line L1519 (248, -39) -> (248, -57)
  line L1520 (38, -20.5) -> (5, -20.5)
  line L1521 (5, -20.5) -> (5, -37.5)
  line L1522 (5, -37.5) -> (38, -37.5)
  line L1523 (38, -37.5) -> (38, -20.5)
  line L1524 (76, -18.5009) -> (185.9026, -18.5009)
  line L1525 (185.9026, -18.5009) -> (185.9026, -1)
  line L1526 (185.9026, -1) -> (76, -1)
  line L1527 (76, -1) -> (76, -18.5009)
  constraint horizontal L1492
  constraint vertical L1493
  constraint horizontal L1494
  constraint vertical L1495
  constraint horizontal L1496
  constraint vertical L1497
  constraint horizontal L1498
  constraint vertical L1499
  constraint horizontal L1500
  constraint vertical L1501
  constraint horizontal L1502
  constraint vertical L1503
  constraint horizontal L1504
  constraint vertical L1505
  constraint horizontal L1506
  constraint vertical L1507
  constraint horizontal L1508
  constraint vertical L1509
  constraint horizontal L1510
  constraint vertical L1511
  constraint horizontal L1512
  constraint vertical L1513
  constraint horizontal L1514
  constraint vertical L1515
  constraint horizontal L1516
  constraint vertical L1517
  constraint horizontal L1518
  constraint vertical L1519
  constraint horizontal L1520
  constraint vertical L1521
  constraint horizontal L1522
  constraint vertical L1523
  constraint horizontal L1524
  constraint vertical L1525
  constraint horizontal L1526
  constraint vertical L1527
extrude "Extrude13" cut sketch "Sketch2" against normal blind 3.5 contours L1492 L1493 L1494 L1495 L1496 L1497 L1498 L1499 L1500 L1501 L1502 L1503 L1504 L1505 L1506 L1507 L1508 L1509 L1510 L1511 bodies 2
extrude "Extrude14" cut sketch "Sketch2" against normal blind 3.5 contours L1512 L1513 L1514 L1515 L1516 L1517 L1518 L1519 bodies 2
extrude "Extrude15" cut sketch "Sketch2" against normal blind 3.5 contours L1520 L1521 L1522 L1523 bodies 2
extrude "Extrude16" cut sketch "Sketch2" against normal blind 3.5 contours L1524 L1525 L1526 L1527 bodies 2
fillet "Fillet1" radius 5 1 edges at (284, 95, -1.75) on bodies 2
fillet "Fillet2" radius 5 1 edges at (250, 95, -1.75) on bodies 2
fillet "Fillet3" radius 5 1 edges at (248, 57, -1.75) on bodies 2
fillet "Fillet4" radius 5 1 edges at (281, 57, -1.75) on bodies 2
fillet "Fillet5" radius 5 1 edges at (5, 37.5, -1.75) on bodies 2
fillet "Fillet6" radius 5 1 edges at (38, 37.5, -1.75) on bodies 2
fillet "Fillet7" radius 5 1 edges at (185.9026, 18.5009, -1.75) on bodies 2
fillet "Fillet8" radius 5 1 edges at (76, 18.5009, -1.75) on bodies 2
sketch "Sketch5" plane through (0, 0, 0) normal (0, 0, 1) x (1, 0, 0)
